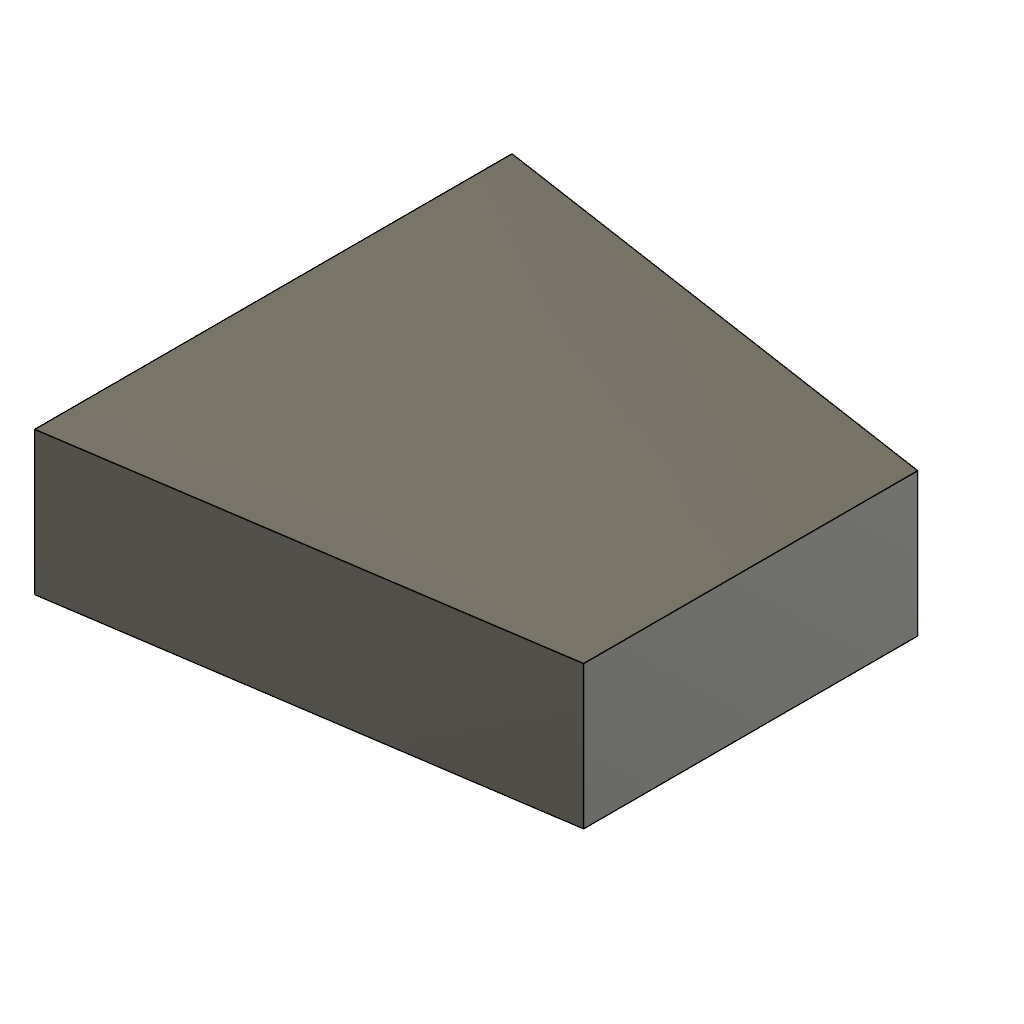
Final form (Autodesk Fusion 360 design; units mm, degrees)
part number: 2026-10-18-12-33-03-868
Autodesk Fusion 360 part; units mm, degrees
sketch "Sketch1" plane through (0, 0, 0) normal (0, 1, 0) x (1, 0, 0)
  line L0 (50, -50) -> (-50, -50)
  line L1 (-50, -50) -> (-50, 50)
  line L2 (-50, 50) -> (50, 50)
  line L3 (50, 50) -> (50, -50)
  line L4 (50, -50) -> (-50, 50) construction
  line L5 (-50, -50) -> (50, 50) construction
  line L6 (-50, 50) -> (50, 35)
  line L7 (-50, -50) -> (50, -35)
  constraint horizontal L0
  constraint perpendicular L0 L1
  constraint parallel L0 L2
  constraint parallel L1 L3
  constraint coincident L4 origin
  constraint coincident L5 origin
  constraint coincident L3 L6.end
extrude "Extrude1" add sketch "Sketch1" along normal blind 10 contours L1 L3 L6 L7
extrude "Extrude2" add 1 faces at (-16.6667, 10, -11.6667) along direction (0, 1, 0) blind 20
shell "Shell1" thickness 5 removed faces 0 bodies 1
